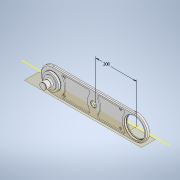
# Autodesk Inventor part: 1.2_2_SideArmClose
Saved by Autodesk Inventor 2021 (Build 250183000, 183)
## iProperties
Created: 2025-11-12
Part Number: 1.2_2_SideArmClose
Material: ABS Plastic
Document SubType Name: Modeling
Designer: Admin
Density: 1.06 g/cm^3
Appearance: Smooth - White
Mass: 507.963 g
Surface Area: 1359.49 cm^2
Volume: 479.21 cm^3
Author: Admin
Autodesk Inventor part; units mm, degrees
ref_plane "YZ Plane" through (0, 0, 0) normal (1, 0, 0) x (0, 1, 0)
ref_plane "XY Plane" through (0, 0, 0) normal (0, 0, 1) x (1, 0, 0)
sketch "Sketch1" plane through (0, 0, 0) normal (0, 0, 1) x (1, 0, 0)
  line L0 (0, 0) -> (400, 0) construction
  line L1 (0, -60) -> (400, -60)
  line L2 (400, 60) -> (0, 60)
  arc A0 (0, 60) -> (0, -60) centre (0, 0) ccw
  arc A1 (400, -60) -> (400, 60) centre (400, 0) ccw
  point P0 (200, 0)
  dimension "d0" = 400
  dimension "d1" = 60
  constraints: 8 end point, 4 point on circle, 4 tangent, 2 centre point, 1 horizontal, 1 midpoint, 1 parallel
  measures "d0" distance of L0.start L0.end
  measures "d1" radius of A0
extrude "Extrusion1" add sketch "Sketch1" along normal blind 11
sketch "Sketch2" plane through (0, 0, 0) normal (0, 1, 0) x (-1, 0, 0)
  line L0 (-400, 11) -> (0, 11) projected
  line L1 (0, 11) -> (0, 22)
  line L2 (0, 22) -> (-40, 22)
  line L3 (-40, 22) -> (-40, 12)
  line L4 (-40, 12) -> (-41, 12)
  line L5 (-41, 12) -> (-41, 11)
  point P0 (0, 0)
  dimension "d4" = 11
  dimension "d5" = 1
  dimension "d6" = 1
  dimension "d7" = 40
  constraints: 10 end point, 4 perpendicular, 1 point on line, 1 vertical
  measures "d4" distance between parallel lines of L2 L0
  measures "d5" distance of L4.end L5.end
  measures "d6" distance of L3.end L4.end
  measures "d7" distance of L1.end L2.end
revolve "Revolution1" add sketch "Sketch2" angle 360 about axis through (0, 0, 11) along (0, 0, 1)
sketch "Sketch3" plane through (0, 0, 0) normal (0, 0, -1) x (-1, 0, 0)
  line L0 (32, 32) -> (-32, 32)
  line L1 (-32, 32) -> (-32, -32)
  line L2 (-32, -32) -> (32, -32)
  line L3 (32, -32) -> (32, 32)
  line L4 (32, 32) -> (-32, -32) construction
  line L5 (-32, 32) -> (32, -32) construction
  point P0 (0, 0)
  dimension "d9" = 64
  constraints: 12 end point, 2 midpoint, 2 parallel, 2 perpendicular, 1 horizontal
  measures "d9" distance of L1.end L2.end
extrude "Extrusion2" cut sketch "Sketch3" against normal blind 5
sketch "Sketch4" plane through (0, 0, 5) normal (0, 0, -1) x (-1, 0, 0)
  point P0 (0, 0)
  point P1 (0, 0)
  constraints: 1 coincident
hole "Hole1" at (0, 0, 5) direction (0, 0, 1) diameter 40 end through all counterbore diameter 52 counterbore depth 3
sketch "Sketch5" plane through (0, 0, 5) normal (0, 0, -1) x (-1, 0, 0)
  circle A0 centre (0, 0) radius 35 construction
  line L0 (24.7487, -24.7487) -> (-24.7487, -24.7487) construction
  line L1 (-24.7487, -24.7487) -> (-24.7487, 24.7487) construction
  line L2 (-24.7487, 24.7487) -> (24.7487, 24.7487) construction
  line L3 (24.7487, 24.7487) -> (24.7487, -24.7487) construction
  line L4 (24.7487, -24.7487) -> (-24.7487, 24.7487) construction
  line L5 (-24.7487, -24.7487) -> (24.7487, 24.7487) construction
  point P0 (-24.7487, 24.7487)
  point P1 (24.7487, 24.7487)
  dimension "d19" = 70
  constraints: 12 end point, 3 coincident, 3 point on circle, 2 midpoint, 2 parallel, 2 perpendicular, 1 centre point, 1 horizontal
  measures "d19" diameter of A0
hole "Hole2" [suppressed]
sketch "Sketch7" plane through (0, 0, 0) normal (0, 0, 1) x (1, 0, 0)
  arc A0 (400, -60) -> (400, 60) centre (400, 0) ccw projected
  circle A1 centre (400, 0) radius 60
  point P0 (0, 0)
  constraints: 1 coincident, 3 other
extrude "Extrusion3" add sketch "Sketch7" against normal blind 3
sketch "Sketch6" plane through (0, 0, 0) normal (0, 1, 0) x (-1, 0, 0)
  line L0 (-400, -5) -> (-448, -5)
  line L1 (-448, -5) -> (-448, 1)
  line L2 (-448, 1) -> (-450, 1)
  line L3 (-450, 1) -> (-450, 11)
  line L4 (-400, 11) -> (-460, 11) projected
  line L5 (-400, 11) -> (-400, -5)
  line L6 (-672, 0) -> (112, 0) projected
  point P0 (0, 0)
  point P1 (-500, -12.1629)
  dimension "d27" = 50
  dimension "d28" = 10
  dimension "d29" = 2
  dimension "d33" = 5
  constraints: 12 end point, 2 perpendicular, 2 vertical, 1 horizontal, 1 point on line
  measures "d27" distance between parallel lines of L5 L3
  measures "d28" distance of L2.end L3.end
  measures "d29" distance of L1.end L2.end
  measures "d33" distance between parallel lines of L6 L0
revolve "Revolution2" cut sketch "Sketch6" angle 360 about axis through (400, 0, 11) along (0, 0, -1)
sketch "Sketch8" plane through (0, 0, 0) normal (0, 0, 1) x (1, 0, 0)
  line L0 (0, -60) -> (400, -60) projected
  line L1 (400, 60) -> (0, 60) projected
  line L2 (65, -60) -> (40, -60)
  line L3 (40, -60) -> (40, 60)
  line L4 (40, 60) -> (65, 60)
  line L5 (65, 60) -> (65, -60)
  line L6 (340, -60) -> (315, -60)
  line L7 (315, -60) -> (315, 60)
  line L8 (315, 60) -> (340, 60)
  line L9 (340, 60) -> (340, -60)
  line L10 (0, 84) -> (0, -84) projected
  point P0 (0, 0)
  point P1 (400, 0)
  point P2 (340, -60)
  point P3 (340, 60)
  point P4 (315, -60)
  dimension "d34" = 60
  dimension "d35" = 25
  dimension "d36" = 25
  dimension "d37" = 40
  constraints: 16 end point, 4 parallel, 4 point on line, 2 horizontal, 2 perpendicular
  measures "d34" distance from line of point (400, 0) L9
  measures "d35" distance between parallel lines of L7 L9
  measures "d36" distance between parallel lines of L3 L5
  measures "d37" distance between parallel lines of L10 L3
extrude "Extrusion4" [suppressed]
chamfer "Chamfer1" distance 4 angle 45 4 edges at (200, -60, 11) (460, 0, 11) (200, 60, 11) (-60, 0, 11)
sketch "Sketch9" plane through (0, 0, 0) normal (0, 0, 1) x (1, 0, 0)
  line L0 (-164, 0) -> (564, 0) projected
  point P0 (0, 0)
  point P1 (200, 0)
  point P2 (400, 0)
  dimension "d43" = 200
  constraints: 1 midpoint
  measures "d43" distance of point (200, 0) point (400, 0)
sketch "Sketch10" plane through (0, 0, 0) normal (0, 1, 0) x (-1, 0, 0)
  line L0 (-400, 0) -> (0, 0) projected
  line L1 (-200, 0) -> (-200, 11)
  line L2 (0, 11) -> (-400, 11) projected
  line L3 (-200, 0) -> (-215, 0)
  line L4 (0, 0) -> (-400, 0) projected
  line L5 (-215, 0) -> (-215, 7)
  line L6 (-215, 7) -> (-214, 7)
  line L7 (-214, 7) -> (-214, 11)
  line L8 (-200, 11) -> (-214, 11)
  line L9 (-400, 11) -> (0, 11) projected
  point P0 (-215, 0)
  dimension "d44" = 15
  dimension "d45" = 1
  dimension "d46" = 7
  constraints: 12 end point, 2 midpoint, 2 perpendicular, 2 point on line, 1 collinear, 1 vertical
  measures "d44" distance between parallel lines of L5 L1
  measures "d45" distance of L5.end L6.end
  measures "d46" distance of L3.end L5.end
revolve "Revolution3" cut sketch "Sketch10" angle 360 about axis through (200, 0, 0) along (0, 0, 1)
sketch "Sketch11" plane through (0, 0, 11) normal (0, 0, 1) x (1, 0, 0)
  circle A0 centre (0, 0) radius 60
  circle A1 centre (200, 0) radius 14 projected
  circle A2 centre (400, 0) radius 60
  line L0 (400, 60) -> (0, 60) projected
  arc A3 (400, 60) -> (400, -60) centre (400, 0) ccw projected
  line L1 (33.1662, -50) -> (366.8338, -50)
  line L2 (366.8338, 50) -> (33.1662, 50)
  line L3 (0, -60) -> (400, -60) projected
  circle A4 centre (230, 0) radius 60
  circle A5 centre (170, 0) radius 60
  point P0 (200, 51.9615)
  point P1 (200, -51.9615)
  point P2 (196.8338, -50)
  point P3 (196.8338, 50)
  point P4 (203.1662, 50)
  point P5 (203.1662, -50)
  point P6 (263.1662, 50)
  point P7 (263.1662, -50)
  point P8 (136.8338, 50)
  point P9 (136.8338, -50)
  dimension "d48" = 10
  dimension "d49" = 10
  dimension "d52" = 30
  dimension "d53" = 30
  constraints: 5 point on circle, 4 centre point, 4 end point, 3 tangent, 1 coincident, 1 horizontal, 1 parallel
  measures "d48" distance between parallel lines of L0 L2
  measures "d49" distance between parallel lines of L3 L1
  measures "d52" distance of A1.centre A4.centre
  measures "d53" distance of A5.centre A1.centre
extrude "Extrusion5" cut sketch "Sketch11" against normal blind 5 contours A0 L2 A5 L1 | L2 A4 L1 A5 | L2 A4 L1 A5 | L2 A2 L1 A4 picked at (130.2404, 1.7887) picked at (268.6624, -9.719)
sketch "Sketch12" plane through (0, 0, 22) normal (0, 0, 1) x (1, 0, 0)
  point P0 (0, 0)
sketch "Sketch13" plane through (0, 0, 0) normal (0, 1, 0) x (-1, 0, 0)
  line L0 (40, 22) -> (-40, 22) projected
  line L1 (0, 22) -> (30, 22)
  line L2 (30, 25) -> (17, 25)
  line L3 (17, 25) -> (17, 35)
  line L4 (17, 35) -> (15, 35)
  line L5 (15, 35) -> (15, 56)
  line L6 (15, 56) -> (14.3, 56)
  line L7 (14.3, 56) -> (14.3, 57.6)
  line L8 (14.3, 57.6) -> (15, 57.6)
  line L9 (15, 57.6) -> (15, 59.7)
  line L10 (15, 59.7) -> (0, 59.7)
  line L11 (0, 59.7) -> (0, 22)
  line L12 (30, 22) -> (30, 25)
  line L13 (0, -15.1) -> (0, 69.6) projected
  point P0 (0, 0)
  dimension "d54" = 30
  dimension "d55" = 17
  dimension "d56" = 15
  dimension "d58" = 1.6
  dimension "d59" = 2.1
  dimension "d60" = 21
  dimension "d61" = 10
  dimension "d62" = 3
  dimension "d84" = 14.3
  constraints: 24 end point, 8 perpendicular, 3 point on line, 1 horizontal, 1 midpoint, 1 vertical
  measures "d54" distance between parallel lines of L11 L12
  measures "d55" distance between parallel lines of L11 L3
  measures "d56" distance between parallel lines of L11 L5
  measures "d58" distance of L6.end L7.end
  measures "d59" distance from line of L10 L7.end
  measures "d60" distance of L4.end L5.end
  measures "d61" distance of L2.end L3.end
  measures "d62" distance of L1.end L2.start
  measures "d84" distance between parallel lines of L11 L7
revolve "Revolution4" add sketch "Sketch13" angle 360 about axis through (0, 0, -10) along (0, 0, 1)
sketch "Sketch14" plane through (0, 0, 6) normal (0, 0, 1) x (1, 0, 0)
  line L0 (52.5, 91.2812) -> (52.5, -109.7408)
  line L1 (327.5, 121.5586) -> (327.5, -103.2883)
  line L2 (0, -156.0007) -> (0, 167.8185) projected
  line L3 (-164, 0) -> (564, 0) projected
  point P0 (0, 0)
  point P1 (400, 0)
  point P2 (52.5, 40)
  point P3 (52.5, -40)
  point P4 (327.5, 40)
  point P5 (327.5, -40)
  dimension "d64" = 52.5
  dimension "d65" = 72.5
  dimension "d66" = 40
  dimension "d67" = 40
  dimension "d68" = 40
  dimension "d69" = 40
  constraints: 4 end point, 4 point on line, 1 parallel, 1 vertical
  measures "d64" distance between parallel lines of L0 L2
  measures "d65" distance from line of point (400, 0) L1
  measures "d66" distance from line of L3 point (52.5, 40)
  measures "d67" distance from line of L3 point (52.5, -40)
  measures "d68" distance from line of L3 point (327.5, -40)
  measures "d69" distance from line of point (327.5, 40) L3
hole "Hole3" at (52.5, 40, 6) at (52.5, -40, 6) at (327.5, -40, 6) at (327.5, 40, 6) direction (0, 0, -1) diameter 6.6 end through all counterbore diameter 11 counterbore depth 2 clearance for "Socket Head Cap Screw ISO 4762" size "M6" standard "ISO"
ref_plane "Work Plane1" through (0, -15, 45.5) normal (0, 1, 0) x (-1, 0, 0)
sketch "Sketch16" plane through (0, -15, 45.5) normal (0, 1, 0) x (-1, 0, 0)
  line L0 (0, 5) -> (0, -5) construction
  line L1 (-4, 5) -> (-4, -5)
  line L2 (4, -5) -> (4, 5)
  arc A0 (4, 5) -> (-4, 5) centre (0, 5) ccw
  arc A1 (-4, -5) -> (4, -5) centre (0, -5) ccw
  line L3 (-17, -10.5) -> (17, -10.5) projected
  point P0 (0, -45.5)
  point P1 (0, 0)
  point P2 (0, -10.5)
  dimension "d79" = 8
  dimension "d80" = 10
  dimension "d81" = 10.5
  constraints: 8 end point, 4 point on circle, 4 tangent, 2 centre point, 2 midpoint, 1 parallel, 1 point on line, 1 vertical
  measures "d79" distance between parallel lines of L1 L2
  measures "d80" distance of L0.start L0.end
  measures "d81" distance from line of L3 point (0, 0)
extrude "Extrusion7" [suppressed]
fillet "Fillet2" radius 0.5 1 edges at (350, 0, 1)
fillet "Fillet3" radius 0.5 1 edges at (-40, 0, 12)
fillet "Fillet4" radius 0.2 1 edges at (185, 0, 7)
fillet "Fillet5" radius 10 4 edges at (196.8338, 50, 8.5) (203.1662, 50, 8.5) (196.8338, -50, 8.5) (203.1662, -50, 8.5)
fillet "Fillet6" radius 10 2 edges at (366.8338, -50, 8.5) (366.8338, 50, 8.5)
fillet "Fillet6" radius 7 2 edges at (33.1662, 50, 8.5) (33.1662, -50, 8.5)
chamfer "Chamfer2" distance 1 angle 45 3 edges at (186, 0, 11) (185, 0, 0) (350, 0, 11)
equation "\"d67\" = d66"
equation "\"d68\" = d67"
equation "\"d69\" = d66"
body "Solid1"
